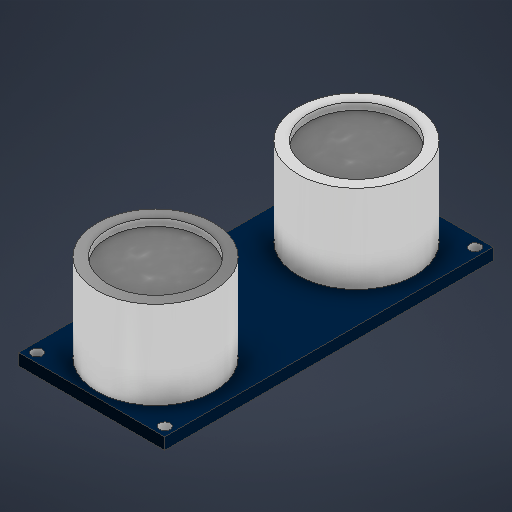
# Autodesk Inventor part: HC-SR04
Saved by Autodesk Inventor 2026.2 (Build 302298000, 298)
## iProperties
Created: 2025-11-11
Part Number: HC-SR04
Material: 일반
Document SubType Name: Modeling
Designer: work
Density: 1 g/cm^3
Appearance: 기본값
Author: work
Autodesk Inventor part; units mm, degrees
ref_plane "YZ Plane" through (0, 0, 0) normal (1, 0, 0) x (0, 1, 0)
ref_plane "XZ Plane" through (0, 0, 0) normal (0, 1, 0) x (-1, 0, 0)
ref_plane "XY Plane" through (0, 0, 0) normal (0, 0, 1) x (1, 0, 0)
sketch "스케치1" plane through (0, 0, 0) normal (0, 1, 0) x (-1, 0, 0)
  line L0 (0, 0) -> (20, 0)
  line L1 (20, 0) -> (20, -45)
  line L2 (20, -45) -> (0, -45)
  line L3 (0, -45) -> (0, 0)
  line L4 (20, -22.5) -> (0, -22.5) construction
  line L5 (10, 0) -> (10, -45) construction
  circle A0 centre (18.75, -1.25) radius 0.75
  circle A1 centre (18.75, -43.75) radius 0.75
  circle A2 centre (1.25, -1.25) radius 0.75
  circle A3 centre (1.25, -43.75) radius 0.75
  dimension "d0" = 20
  dimension "d1" = 45
  dimension "d2" = 1.5
  dimension "d5" = 42.5
  dimension "d6" = 17.5
  constraints: 12 end point, 4 centre point, 4 midpoint, 3 symmetric about line, 2 parallel, 1 horizontal, 1 perpendicular, 3 other
  measures "d0" distance of L1.end L2.end
  measures "d1" distance of L0.end L1.end
  measures "d2" diameter of A0
  measures "d5" distance of A1.centre A0.centre
  measures "d6" distance of A2.centre A0.centre
extrude "돌출1" add sketch "스케치1" along normal blind 1.6
sketch "스케치2" plane through (0, 1.6, 0) normal (0, 1, 0) x (1, 0, 0)
  line L0 (-20, 45) -> (-20, 0) projected
  line L1 (-20, 22.5) -> (0, 22.5) construction
  line L2 (0, 0) -> (0, 45) projected
  circle A0 centre (-10, 8.74) radius 8
  circle A1 centre (-10, 36.26) radius 8
  line L3 (0, 45) -> (-20, 45) projected
  line L4 (-10, 45) -> (-10, 0) construction
  line L5 (-20, 0) -> (0, 0) projected
  dimension "d9" = 16
  dimension "d10" = 27.52
  constraints: 4 end point, 4 midpoint, 2 centre point, 1 point on line, 1 symmetric about line, 1 other
  measures "d9" diameter of A0
  measures "d10" distance of A1.centre A0.centre
extrude "돌출2" add sketch "스케치2" along normal blind 12 contours A0 | A1
sketch "스케치3" plane through (-10, 13.6, -8.74) normal (0, 1, 0) x (1, 0, 0)
  line L0 (-10, 36.26) -> (-10, -8.74) projected
  line L1 (-10, 13.76) -> (10, 13.76)
  line L2 (10, -8.74) -> (10, 36.26) projected
  circle A0 centre (0, 0) radius 8 projected
  circle A1 centre (0, 0) radius 6.5
  circle A2 centre (0, 27.52) radius 6.5
  circle A3 centre (0, 27.52) radius 8 projected
  dimension "d13" = 1.5
  constraints: 2 centre point, 2 end point, 2 midpoint, 1 coincident, 1 symmetric about line, 1 other
  measures "d13" radial gap between concentric circles of A0 A1
extrude "돌출3" cut sketch "스케치3" against normal blind 1 contours A1 | A2
